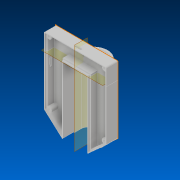
# Autodesk Inventor part: base v5
Saved by Autodesk Inventor 2019 (Build 230136000, 136)
## iProperties
Created: 2019-04-14
Part Number: base v5
Material: Generic
Document SubType Name: Modeling
Designer: --------
Density: 1 g/cm^3
Appearance: Default
Author: --------
Autodesk Inventor part; units mm, degrees
ref_plane "YZ Plane" through (0, 0, 0) normal (1, 0, 0) x (0, 1, 0)
ref_plane "XZ Plane" through (0, 0, 0) normal (0, 1, 0) x (-1, 0, 0)
ref_plane "XY Plane" through (0, 0, 0) normal (0, 0, 1) x (1, 0, 0)
sketch "Sketch1" plane through (0, 0, 0) normal (0, 0, 1) x (1, 0, 0)
  line L0 (0, 0) -> (185, 0)
  line L1 (185, 0) -> (185, -250)
  line L2 (185, -250) -> (0, -250)
  line L3 (0, -250) -> (0, 0)
  line L4 (92.5, -250) -> (129.5, -250)
  line L5 (185, 0) -> (185, -200)
  line L6 (185, -200) -> (129.5, -250)
  line L7 (92.5, -250) -> (55.5, -250)
  line L8 (0, 0) -> (0, -200)
  line L9 (0, -200) -> (55.5, -250)
  line L10 (55.5, -250) -> (55.5, -50)
  line L11 (55.5, -50) -> (129.5, -50)
  line L12 (129.5, -50) -> (129.5, -250)
  dimension "d0" = 185
  dimension "d1" = 250
  dimension "d2" = 37
  dimension "d3" = 200
  dimension "d4" = 37
  dimension "d5" = 200
  dimension "d6" = 200
  constraints: 26 end point, 5 perpendicular, 4 point on line, 1 horizontal, 1 midpoint, 1 vertical
  measures "d0" distance of L0.start L0.end
  measures "d1" distance of L0.end L1.end
  measures "d2" distance of L4.start L4.end
  measures "d3" distance of L0.end L5.end
  measures "d4" distance of L4.start L7.end
  measures "d5" distance of L0.start L8.end
  measures "d6" distance of L7.end L10.end
extrude "Extrusion1" add sketch "Sketch1" along normal blind 10 contours L0 L1 L6 L12 L11 L10 L9 L3
sketch "Sketch2" plane through (0, 0, 10) normal (0, 0, 1) x (1, 0, 0)
  line L0 (0, 0) -> (0, -200) projected
  line L1 (0, -200) -> (55.5, -250) projected
  line L2 (55.5, -250) -> (55.5, -50) projected
  line L3 (55.5, -50) -> (129.5, -50) projected
  line L4 (129.5, -50) -> (129.5, -250) projected
  line L5 (129.5, -250) -> (185, -200) projected
  line L6 (185, -200) -> (185, 0) projected
  line L7 (185, 0) -> (0, 0) projected
  line L8 (5, -197.7747) -> (5, -5)
  line L9 (5, -5) -> (180, -5)
  line L10 (180, -5) -> (180, -197.7747)
  line L11 (180, -197.7747) -> (134.5, -238.7657)
  line L12 (134.5, -238.7657) -> (134.5, -45)
  line L13 (134.5, -45) -> (50.5, -45)
  line L14 (50.5, -45) -> (50.5, -238.7657)
  line L15 (50.5, -238.7657) -> (5, -197.7747)
  dimension "d9" = 5
  constraints: 16 end point, 7 other
  measures "d9" distance between parallel lines of L0 L8
extrude "Extrusion2" add sketch "Sketch2" along normal blind 20
sketch "Sketch3" plane through (0, 0, 30) normal (0, 0, 1) x (1, 0, 0)
  line L0 (5, -5) -> (180, -5) projected
  line L1 (180, -5) -> (180, -197.7747) projected
  line L2 (180, -197.7747) -> (134.5, -238.7657) projected
  line L3 (134.5, -238.7657) -> (134.5, -45) projected
  line L4 (134.5, -45) -> (50.5, -45) projected
  line L5 (50.5, -45) -> (50.5, -238.7657) projected
  line L6 (50.5, -238.7657) -> (5, -197.7747) projected
  line L7 (5, -197.7747) -> (5, -5) projected
  line L8 (0, 0) -> (0, -200) projected
  line L9 (0, -200) -> (55.5, -250) projected
  line L10 (55.5, -250) -> (55.5, -50) projected
  line L11 (55.5, -50) -> (129.5, -50) projected
  line L12 (129.5, -50) -> (129.5, -250) projected
  line L13 (129.5, -250) -> (185, -200) projected
  line L14 (185, -200) -> (185, 0) projected
  line L15 (185, 0) -> (0, 0) projected
  line L16 (2, -199.1099) -> (2, -2)
  line L17 (2, -2) -> (183, -2)
  line L18 (183, -2) -> (183, -199.1099)
  line L19 (183, -199.1099) -> (131.5, -245.5063)
  line L20 (131.5, -245.5063) -> (131.5, -48)
  line L21 (131.5, -48) -> (53.5, -48)
  line L22 (53.5, -48) -> (53.5, -245.5063)
  line L23 (53.5, -245.5063) -> (2, -199.1099)
  dimension "d12" = 2
  constraints: 16 end point, 7 other
  measures "d12" distance between parallel lines of L8 L16
extrude "Extrusion3" add sketch "Sketch3" along normal blind 5 contours L15 L14 L13 L12 L11 L10 L9 L8
sketch "Sketch4" plane through (0, 0, 10) normal (0, 0, 1) x (1, 0, 0)
  line L0 (180, -5) -> (5, -5) projected
  line L1 (5, -5) -> (5, -197.7747) projected
  line L2 (5, -197.7747) -> (50.5, -238.7657) projected
  line L3 (50.5, -238.7657) -> (50.5, -45) projected
  line L4 (50.5, -45) -> (134.5, -45) projected
  line L5 (134.5, -45) -> (134.5, -238.7657) projected
  line L6 (134.5, -238.7657) -> (180, -197.7747) projected
  line L7 (180, -197.7747) -> (180, -5) projected
  line L8 (183, -2) -> (2, -2) projected
  line L9 (2, -2) -> (2, -199.1099) projected
  line L10 (2, -199.1099) -> (53.5, -245.5063) projected
  line L11 (53.5, -245.5063) -> (53.5, -48) projected
  line L12 (53.5, -48) -> (131.5, -48) projected
  line L13 (131.5, -48) -> (131.5, -245.5063) projected
  line L14 (131.5, -245.5063) -> (183, -199.1099) projected
  line L15 (183, -199.1099) -> (183, -2) projected
  line L16 (5, -5) -> (180, -5) projected
  line L17 (180, -5) -> (180, -197.7747) projected
  line L18 (180, -197.7747) -> (134.5, -238.7657) projected
  line L19 (134.5, -238.7657) -> (134.5, -45) projected
  line L20 (134.5, -45) -> (50.5, -45) projected
  line L21 (50.5, -45) -> (50.5, -238.7657) projected
  line L22 (50.5, -238.7657) -> (5, -197.7747) projected
  line L23 (5, -197.7747) -> (5, -5) projected
  line L24 (5, -5) -> (10, -5)
  line L25 (10, -5) -> (10, -10)
  arc A0 (5, -15) -> (15, -5) centre (10, -10) ccw
  circle A1 centre (10, -10) radius 2.5
  line L26 (15, -5) -> (5, -5)
  line L27 (5, -5) -> (5, -15)
  point P0 (0, 0)
  dimension "d16" = 5
  dimension "d17" = 5
  dimension "d18" = 5
  constraints: 9 end point, 3 point on circle, 3 point on line, 2 centre point, 2 coincident, 2 perpendicular, 1 collinear
  measures "d16" distance of L16.start L24.end
  measures "d17" distance of L24.end L25.end
  measures "d18" diameter of A1
extrude "Extrusion4" add sketch "Sketch4" along normal blind 20 contours A0 L1 L0
ref_plane "Work Plane1" through (92.5, -200, 0) normal (1, 0, 0) x (0, 0, -1)
mirror "Mirror1" about plane through (92.5, -200, 0) normal (1, 0, 0) of "Extrusion4"
fillet "Fillet1" radius 1 2 edges at (55.5, -250, 17.5) (129.5, -250, 17.5)
sketch "Sketch7" plane through (0, 0, 30) normal (0, 0, 1) x (1, 0, 0)
  circle A0 centre (175, -10) radius 2.5 projected
  circle A1 centre (10, -10) radius 2.5 projected
  line L0 (183, -2) -> (2, -2) projected
  line L1 (2, -2) -> (2, -199.1099) projected
  line L2 (2, -199.1099) -> (53.5, -245.5063) projected
  line L3 (53.5, -245.5063) -> (53.5, -48) projected
  line L4 (53.5, -48) -> (131.5, -48) projected
  line L5 (131.5, -48) -> (131.5, -245.5063) projected
  line L6 (131.5, -245.5063) -> (183, -199.1099) projected
  line L7 (183, -199.1099) -> (183, -2) projected
  line L8 (15, -5) -> (170, -5) projected
  arc A2 (170, -5) -> (180, -15) centre (175, -10) ccw projected
  line L9 (180, -15) -> (180, -197.7747) projected
  line L10 (180, -197.7747) -> (134.5, -238.7657) projected
  line L11 (134.5, -238.7657) -> (134.5, -45) projected
  line L12 (134.5, -45) -> (50.5, -45) projected
  line L13 (50.5, -45) -> (50.5, -238.7657) projected
  line L14 (50.5, -238.7657) -> (5, -197.7747) projected
  line L15 (5, -197.7747) -> (5, -15) projected
  arc A3 (5, -15) -> (15, -5) centre (10, -10) ccw projected
  point P0 (0, 0)
extrude "Extrusion7" cut sketch "Sketch7" against normal blind 30 contours A0 | A1
fillet "Fillet2" radius 2 4 edges at (185, 0, 17.5) (0, 0, 17.5) (185, -200, 17.5) (0, -200, 17.5)
sketch "Sketch10" plane through (0, 0, 0) normal (0, 0, -1) x (-1, 0, 0)
  arc A0 (-0.6613, -200.5958) -> (0, -199.1099) centre (-2, -199.1099) ccw projected
  line L0 (0, -2) -> (0, -199.1099) projected
  arc A1 (0, -2) -> (-2, 0) centre (-2, -2) ccw projected
  line L1 (-183, 0) -> (-2, 0) projected
  arc A2 (-183, 0) -> (-185, -2) centre (-183, -2) ccw projected
  line L2 (-185, -199.1099) -> (-185, -2) projected
  arc A3 (-185, -199.1099) -> (-184.3387, -200.5958) centre (-183, -199.1099) ccw projected
  line L3 (-131.1693, -248.4961) -> (-184.3387, -200.5958) projected
  arc A4 (-131.1693, -248.4961) -> (-129.5, -247.7531) centre (-130.5, -247.7531) ccw projected
  line L4 (-129.5, -50) -> (-129.5, -247.7531) projected
  line L5 (-55.5, -50) -> (-129.5, -50) projected
  line L6 (-55.5, -247.7531) -> (-55.5, -50) projected
  arc A5 (-55.5, -247.7531) -> (-53.8307, -248.4961) centre (-54.5, -247.7531) ccw projected
  line L7 (-0.6613, -200.5958) -> (-53.8307, -248.4961) projected
  circle A6 centre (-175, -10) radius 2.5 projected
  circle A7 centre (-10, -10) radius 2.5 projected
  arc A8 (-55.5, -247.7531) -> (-53.8307, -248.4961) centre (-54.5, -247.7531) ccw projected
  line L8 (-54.5, -247.7531) -> (-55.5, -247.7531)
  line L9 (-54.5, -247.7531) -> (-54.5, -237.7531)
  line L10 (-54.5, -237.7531) -> (-50.5, -237.7531)
  line L11 (-50.5, -237.7531) -> (-50.5, -50)
  line L12 (-50.5, -45) -> (-50.5, -238.7657) projected
  line L13 (-50.5, -50) -> (-55.5, -50)
  line L14 (-55.5, -50) -> (-55.5, -237.7531)
  line L15 (-55.5, -247.7531) -> (-55.5, -50) projected
  line L16 (-54.5, -237.7531) -> (-55.5, -237.7531)
  point P0 (0, 0)
  dimension "d37" = 10
  dimension "d38" = 4
  constraints: 14 end point, 3 perpendicular, 2 point on line, 1 horizontal, 1 vertical
  measures "d37" distance of L8.start L9.end
  measures "d38" distance of L9.end L10.end
extrude "Extrusion8" add sketch "Sketch10" along normal blind 20 contours L6 L16 L9 L8 | L6 L13 L11 L10 L16
mirror "Mirror3" about plane through (92.5, -200, 0) normal (1, 0, 0) of "Extrusion8"
sketch "Sketch11" plane through (0, 0, -20) normal (0, 0, -1) x (-1, 0, 0)
  line L0 (-54.5, -237.7531) -> (-50.5, -237.7531) projected
  line L1 (-50.5, -237.7531) -> (-50.5, -50) projected
  line L2 (-50.5, -50) -> (-55.5, -50) projected
  line L3 (-55.5, -50) -> (-55.5, -247.7531) projected
  line L4 (-55.5, -50) -> (-129.5, -50) projected
  line L5 (-92.5, -50) -> (-92.5, -139.3778)
  line L6 (-55.5, -247.7531) -> (-54.5, -247.7531) projected
  line L7 (-54.5, -247.7531) -> (-54.5, -237.7531) projected
  point P0 (0, 0)
  constraints: 2 end point, 1 midpoint, 1 vertical
revolve "Revolution2" add sketch "Sketch11" angle 180 about axis through (92.5, -50, -20) along (0, -1, 0)
ref_plane "Work Plane2" through (2, -50, 0) normal (0, 1, 0) x (1, 0, 0)
split_face "Split1"
sketch "Sketch15" plane through (92.5, -237.7531, -20) normal (0, -1, 0) x (1, 0, 0)
  line L0 (38, 20) -> (42, 20) projected
  line L1 (38, 20) -> (38, 0) projected
  arc A0 (-38, 0) -> (38, 0) centre (0, 0) ccw projected
  line L2 (-38, 20) -> (-38, 0) projected
  line L3 (-42, 20) -> (-38, 20) projected
  line L4 (-42, 20) -> (-42, 0) projected
  arc A1 (-42, 0) -> (42, 0) centre (0, 0) ccw projected
  line L5 (42, 20) -> (42, 0) projected
  line L6 (37, 20) -> (38, 20) projected
  line L7 (37, 20) -> (37, 0) projected
  arc A2 (-37, 0) -> (37, 0) centre (0, 0) ccw projected
  line L8 (-37, 20) -> (-37, 0) projected
  line L9 (-38, 20) -> (-37, 20) projected
  line L10 (-38, 20) -> (-38, 0) projected
  arc A3 (-38, 0) -> (38, 0) centre (0, 0) ccw projected
  line L11 (38, 20) -> (38, 0) projected
  point P0 (-92.5, 20)
extrude "Extrusion10" add sketch "Sketch15" along normal blind 55
sketch "Sketch17" plane through (50.5, -292.7531, 0) normal (0, 0, 1) x (1, 0, 0)
  line L0 (0, 242.7531) -> (0, 0) projected
  line L1 (0, 242.7531) -> (84, 242.7531) projected
  line L2 (84, 0) -> (84, 242.7531) projected
  line L3 (0, 0) -> (84, 0) projected
  line L4 (79, 242.7531) -> (79, 0) projected
  line L5 (5, 242.7531) -> (79, 242.7531) projected
  line L6 (5, 242.7531) -> (5, 0) projected
  line L7 (79, 0) -> (5, 0) projected
  line L8 (5, 242.7531) -> (3, 242.7531) projected
  line L9 (3, 242.7531) -> (3, 47.2469) projected
  line L10 (3, 47.2469) -> (-48.5, 93.6433) projected
  line L11 (-48.5, 93.6433) -> (-48.5, 242.7531) projected
  line L12 (-48.5, 242.7531) -> (-50.5, 242.7531) projected
  line L13 (-50.5, 242.7531) -> (-50.5, 93.6433) projected
  arc A0 (-50.5, 93.6433) -> (-49.8387, 92.1573) centre (-48.5, 93.6433) ccw projected
  line L14 (-49.8387, 92.1573) -> (3.3307, 44.257) projected
  arc A1 (3.3307, 44.257) -> (5, 45) centre (4, 45) ccw projected
  line L15 (5, 45) -> (5, 242.7531) projected
  line L16 (134.5, 242.7531) -> (132.5, 242.7531) projected
  line L17 (132.5, 242.7531) -> (132.5, 93.6433) projected
  line L18 (132.5, 93.6433) -> (81, 47.2469) projected
  line L19 (81, 47.2469) -> (81, 242.7531) projected
  line L20 (81, 242.7531) -> (79, 242.7531) projected
  line L21 (79, 242.7531) -> (79, 45) projected
  arc A2 (79, 45) -> (80.6693, 44.257) centre (80, 45) ccw projected
  line L22 (80.6693, 44.257) -> (133.8387, 92.1573) projected
  arc A3 (133.8387, 92.1573) -> (134.5, 93.6433) centre (132.5, 93.6433) ccw projected
  line L23 (134.5, 93.6433) -> (134.5, 242.7531) projected
  line L24 (5, 242.7531) -> (5, 0) projected
  line L25 (5, 42.5144) -> (48.3013, 17.5144)
  line L26 (79, 242.7531) -> (79, 0) projected
  line L27 (79, 42.5144) -> (35.6987, 17.5144)
  line L28 (42, 30.1806) -> (42, 11.044)
  line L29 (5, 42.5144) -> (79, 42.5144)
  line L30 (5, 42.5144) -> (0, 42.5144)
  line L31 (0, 242.7531) -> (0, 0) projected
  line L32 (79, 42.5144) -> (84, 42.5144)
  line L33 (84, 0) -> (84, 242.7531) projected
  line L34 (0, 0) -> (84, 0) projected
  line L35 (0, 42.5144) -> (84, 42.5144)
  line L36 (84, 42.5144) -> (84, 0)
  line L37 (84, 0) -> (0, 0)
  line L38 (0, 0) -> (0, 42.5144)
  line L39 (79, 42.5144) -> (42, 21.1524)
  line L40 (5, 42.5144) -> (42, 21.1524)
  point P0 (-50.5, 292.7531)
  dimension "d59" = 50
  dimension "d60" = 50
  dimension "d61" = 30
  dimension "d62" = 30
  constraints: 24 end point, 6 point on line, 3 perpendicular, 2 horizontal, 2 parallel, 1 collinear, 1 vertical
  measures "d59" distance of L25.start L25.end
  measures "d60" distance of L27.start L27.end
  measures "d61" angle of L29 L27
  measures "d62" angle of L25 L29
extrude "Extrusion12" cut sketch "Sketch17" against normal blind 70 contours L30 L6 L3 L0 | L25 L27 L4 L3 L6 | L32 L2 L3 L4
sketch "Sketch20" plane through (2, -2, 30) normal (0, 0, 1) x (1, 0, 0)
  line L0 (181, -48) -> (178, -48) projected
  line L1 (181, -48) -> (181, 0) projected
  line L2 (181, 0) -> (0, 0) projected
  line L3 (0, 0) -> (0, -48) projected
  line L4 (3, -48) -> (0, -48) projected
  line L5 (3, -48) -> (3, -13) projected
  arc A0 (3, -13) -> (13, -3) centre (8, -8) ccw projected
  line L6 (13, -3) -> (168, -3) projected
  arc A1 (168, -3) -> (178, -13) centre (173, -8) ccw projected
  line L7 (178, -13) -> (178, -48) projected
  circle A2 centre (8, -8) radius 2.5 projected
  circle A3 centre (173, -8) radius 2.5 projected
  line L8 (181, -48) -> (181, -197.1099) projected
  line L9 (178, -48) -> (178, -195.7747) projected
  line L10 (178, -48) -> (132.5, -48) projected
  line L11 (132.5, -48) -> (132.5, -236.7657) projected
  line L12 (132.5, -236.7657) -> (178, -195.7747) projected
  line L13 (178, -195.7747) -> (178, -48) projected
  line L14 (178, -48) -> (132.5, -48) projected
  line L15 (178, -48) -> (178, -13) projected
  arc A4 (168, -3) -> (178, -13) centre (173, -8) ccw projected
  line L16 (168, -3) -> (13, -3) projected
  arc A5 (3, -13) -> (13, -3) centre (8, -8) ccw projected
  line L17 (3, -13) -> (3, -48) projected
  line L18 (48.5, -48) -> (3, -48) projected
  line L19 (48.5, -48) -> (48.5, -43) projected
  line L20 (48.5, -43) -> (132.5, -43) projected
  line L21 (132.5, -43) -> (132.5, -48) projected
  circle A6 centre (173, -8) radius 2.5 projected
  line L22 (173, -8) -> (172.5839, -195.9995)
  arc A7 (178, -190.8115) -> (169.954, -203.0233) centre (172.5839, -195.9995) ccw
  circle A8 centre (172.5839, -195.9995) radius 2.5
  line L23 (178, -195.7747) -> (178, -48) projected
  line L24 (178, -190.8115) -> (178, -195.7747)
  line L25 (178, -195.7747) -> (169.954, -203.0233)
  point P0 (-2, 2)
  dimension "d74" = 188
  dimension "d75" = 15
  dimension "d76" = 5
  constraints: 6 end point, 2 centre point, 2 coincident, 2 collinear, 2 point on circle, 2 point on line
  measures "d74" distance of L22.start L22.end
  measures "d75" diameter of A7
  measures "d76" diameter of A8
extrude "Extrusion14" add sketch "Sketch20" against normal blind 20 contours L9 L12 A7
mirror "Mirror5" about plane through (92.5, -200, 0) normal (1, 0, 0) of "Extrusion14"
sketch "Sketch21" plane through (183, 0, 0) normal (0, 0, -1) x (-1, 0, 0)
  line L0 (48.5, -50) -> (-2, -50) projected
  line L1 (48.5, -50) -> (53.5, -50) projected
  line L2 (127.5, -50) -> (53.5, -50) projected
  line L3 (127.5, -50) -> (132.5, -50) projected
  line L4 (183, -50) -> (132.5, -50) projected
  line L5 (183, -2) -> (183, -50) projected
  arc A0 (183, -2) -> (181, 0) centre (181, -2) ccw projected
  line L6 (0, 0) -> (181, 0) projected
  arc A1 (0, 0) -> (-2, -2) centre (0, -2) ccw projected
  line L7 (-2, -50) -> (-2, -2) projected
  circle A2 centre (8, -10) radius 2.5 projected
  circle A3 centre (173, -10) radius 2.5 projected
  point P0 (183, 0)
extrude "Extrusion15" add sketch "Sketch21" against normal blind 10 contours A2 | A3
sketch "Sketch22" plane through (183, 0, 0) normal (0, 0, -1) x (-1, 0, 0)
  line L0 (48.5, -50) -> (-2, -50) projected
  line L1 (48.5, -50) -> (53.5, -50) projected
  line L2 (127.5, -50) -> (53.5, -50) projected
  line L3 (127.5, -50) -> (132.5, -50) projected
  line L4 (183, -50) -> (132.5, -50) projected
  line L5 (183, -2) -> (183, -50) projected
  arc A0 (183, -2) -> (181, 0) centre (181, -2) ccw projected
  line L6 (0, 0) -> (181, 0) projected
  arc A1 (0, 0) -> (-2, -2) centre (0, -2) ccw projected
  line L7 (-2, -50) -> (-2, -2) projected
  line L8 (48.5, -245.4955) -> (48.5, -50) projected
  line L9 (48.5, -50) -> (-2, -50) projected
  line L10 (-2, -199.1099) -> (-2, -50) projected
  arc A2 (-2, -199.1099) -> (-1.3387, -200.5958) centre (0, -199.1099) ccw projected
  line L11 (48.5, -245.4955) -> (-1.3387, -200.5958) projected
  line L12 (132.5, -50) -> (132.5, -245.4955) projected
  line L13 (182.3387, -200.5958) -> (132.5, -245.4955) projected
  arc A3 (182.3387, -200.5958) -> (183, -199.1099) centre (181, -199.1099) ccw projected
  line L14 (183, -50) -> (183, -199.1099) projected
  line L15 (183, -50) -> (132.5, -50) projected
  point P0 (183, 0)
sketch "Sketch23" plane through (55.5, -247.7531, 35) normal (0, 0, 1) x (1, 0, 0)
  line L0 (-53.5, 245.7531) -> (127.5, 245.7531) projected
  circle A0 centre (-45.0839, 49.7536) radius 2.5 projected
  line L1 (-2, 197.7531) -> (-5, 197.7531) projected
  line L2 (-5, 197.7531) -> (-5, 8.9875) projected
  line L3 (-5, 8.9875) -> (-42.454, 42.7298) projected
  arc A1 (-42.454, 42.7298) -> (-50.5, 54.9417) centre (-45.0839, 49.7536) ccw projected
  line L4 (-50.5, 54.9417) -> (-50.5, 197.7531) projected
  line L5 (-50.5, 197.7531) -> (-53.5, 197.7531) projected
  line L6 (-53.5, 197.7531) -> (-53.5, 48.6433) projected
  line L7 (-53.5, 48.6433) -> (-2, 2.2469) projected
  line L8 (-2, 2.2469) -> (-2, 197.7531) projected
  line L9 (37, 247.7531) -> (37, 126.7531)
  line L10 (37, 126.7531) -> (27, 126.7531)
  line L11 (27, 126.7531) -> (27, 96.7531)
  line L12 (27, 96.7531) -> (47, 96.7531)
  line L13 (47, 96.7531) -> (47, 126.7531)
  line L14 (47, 126.7531) -> (37, 126.7531)
  point P0 (-55.5, 247.7531)
  dimension "d81" = 121
  dimension "d82" = 10
  dimension "d83" = 30
  dimension "d84" = 20
  constraints: 12 end point, 5 perpendicular, 1 point on line, 1 vertical
  measures "d81" distance of L9.start L9.end
  measures "d82" distance of L9.end L10.end
  measures "d83" distance of L10.end L11.end
  measures "d84" distance of L11.end L12.end
extrude "Extrusion16" cut sketch "Sketch23" against normal through all contours L14 L13 L12 L11 L10
sketch "Sketch24" plane through (2, 0, 0) normal (0, 1, 0) x (1, 0, 0)
  line L0 (0, -35) -> (0, 0) projected
  line L1 (181, -35) -> (0, -35) projected
  line L2 (181, 0) -> (181, -35) projected
  line L3 (181, 0) -> (0, 0) projected
  line L4 (53.5, -35) -> (127.5, -35) projected
  line L5 (90.5, -35) -> (90.5, -25)
  line L6 (51.5, -30) -> (129.5, -30) projected
  line L7 (90.5, -25) -> (83, -25)
  line L8 (83, -25) -> (98, -25)
  line L9 (98, -25) -> (83, -25) construction
  line L10 (98, -22.5) -> (83, -22.5)
  line L11 (83, -27.5) -> (98, -27.5)
  arc A0 (98, -27.5) -> (98, -22.5) centre (98, -25) ccw
  arc A1 (83, -22.5) -> (83, -27.5) centre (83, -25) ccw
  point P0 (-2, 0)
  dimension "d87" = 10
  dimension "d89" = 7.5
  dimension "d90" = 15
  constraints: 14 end point, 4 point on circle, 4 tangent, 2 centre point, 2 equal length, 2 midpoint, 1 horizontal, 1 point on line, 1 vertical
  measures "d87" distance of L5.start L5.end
  measures "d89" distance of L5.end L7.end
  measures "d90" distance of L7.end L8.end
extrude "Extrusion17" cut sketch "Sketch24" against normal blind 10 contours A0 L11 A1 L10
sketch "Sketch25" plane through (0, -199.1099, 0) normal (-1, 0, 0) x (0, 0, 1)
  line L0 (35, 0) -> (0, 0) projected
  line L1 (35, 149.1099) -> (35, 0) projected
  line L2 (35, 197.1099) -> (35, 149.1099) projected
  line L3 (0, 197.1099) -> (35, 197.1099) projected
  line L4 (0, 197.1099) -> (0, 149.1099) projected
  line L5 (0, 149.1099) -> (0, 0) projected
  line L6 (0, 197.1099) -> (35, 197.1099) projected
  line L7 (35, 197.1099) -> (35, 117.1099)
  line L8 (35, 149.1099) -> (35, -48.6433) projected
  line L9 (35, 117.1099) -> (20, 117.1099)
  line L10 (20, 117.1099) -> (23, 117.1099)
  line L11 (20, 117.1099) -> (20, 107.1099)
  line L12 (20, 107.1099) -> (20, 127.1099)
  line L13 (20, 127.1099) -> (20, 107.1099) construction
  line L14 (17, 127.1099) -> (17, 107.1099)
  line L15 (23, 107.1099) -> (23, 127.1099)
  arc A0 (23, 127.1099) -> (17, 127.1099) centre (20, 127.1099) ccw
  arc A1 (17, 107.1099) -> (23, 107.1099) centre (20, 107.1099) ccw
  point P0 (0, 199.1099)
  dimension "d93" = 80
  dimension "d94" = 15
  dimension "d97" = 3
  dimension "d98" = 10
  dimension "d99" = 20
  constraints: 18 end point, 4 point on circle, 4 tangent, 3 point on line, 2 centre point, 2 midpoint, 1 collinear, 1 parallel, 1 perpendicular, 1 vertical
  measures "d93" distance of L2.start L7.end
  measures "d94" distance of L7.end L9.end
  measures "d97" distance of L9.end L10.end
  measures "d98" distance of L9.end L11.end
  measures "d99" distance of L11.end L12.end
extrude "Extrusion18" cut sketch "Sketch25" against normal blind 10 contours A0 L15 A1 L14
sketch "Sketch26" plane through (183, 0, 0) normal (0, 0, -1) x (-1, 0, 0)
  line L0 (48.5, -50) -> (-2, -50) projected
  line L1 (48.5, -50) -> (53.5, -50) projected
  line L2 (127.5, -50) -> (53.5, -50) projected
  line L3 (127.5, -50) -> (132.5, -50) projected
  line L4 (183, -50) -> (132.5, -50) projected
  line L5 (183, -2) -> (183, -50) projected
  arc A0 (183, -2) -> (181, 0) centre (181, -2) ccw projected
  line L6 (0, 0) -> (181, 0) projected
  arc A1 (0, 0) -> (-2, -2) centre (0, -2) ccw projected
  line L7 (-2, -50) -> (-2, -2) projected
  line L8 (98, 0) -> (83, 0) projected
  line L9 (90.5, 0) -> (90.5, -30)
  line L10 (183, -2) -> (183, -50) projected
  line L11 (183, -30) -> (172.25, -30)
  line L12 (-2, -50) -> (-2, -2) projected
  line L13 (-2, -30) -> (8.75, -30)
  point P0 (183, 0)
  dimension "d102" = 30
  dimension "d103" = 10.75
  dimension "d104" = 10.75
  constraints: 6 end point, 2 perpendicular, 2 point on line, 1 midpoint, 1 vertical
  measures "d102" distance of L9.start L9.end
  measures "d103" distance of L11.start L11.end
  measures "d104" distance of L13.start L13.end
hole "Hole1" at (174.25, -30, 0) at (92.5, -30, 0) at (10.75, -30, 0) direction (0, 0, 1) diameter 5 end through all
sketch "Sketch27" plane through (185, -199.1099, 0) normal (1, 0, 0) x (0, 0, -1)
  line L0 (0, 149.1099) -> (-35, 149.1099) projected
  line L1 (-35, 0) -> (-35, 149.1099) projected
  line L2 (0, 0) -> (-35, 0) projected
  line L3 (0, 0) -> (0, 149.1099) projected
  line L4 (-35, 149.1099) -> (90.8925, 149.1099)
  line L5 (0, 149.1099) -> (20, 149.1099) projected
  point P0 (0, 199.1099)
  constraints: 2 end point, 1 collinear
split body "Split2" sketch "Sketch27" result two bodies curves L4 first body at (92.5, -9.1667, 0.5)
body "Solid2"
body "Solid3"
